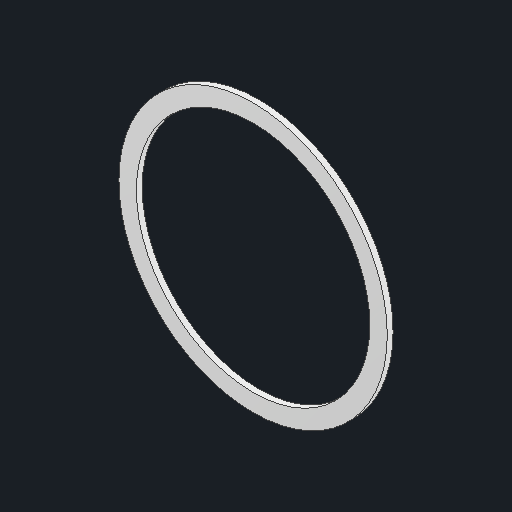
# Autodesk Inventor part: latitude_scale
Saved by Autodesk Inventor 2027.1 (Build 311270010, 270A)
## iProperties
Created: 2026-11-03
Part Number: latitude_scale
Material: Generic
Description: Latitude scale ring
Document SubType Name: Modeling
Designer: Claude (from photos)
Density: 1 g/cm^3
Appearance: Smooth - White
Author: alexg
Autodesk Inventor part; units mm, degrees
ref_plane "YZ Plane" through (0, 0, 0) normal (1, 0, 0) x (0, 1, 0)
ref_plane "XZ Plane" through (0, 0, 0) normal (0, 1, 0) x (-1, 0, 0)
ref_plane "Work Plane1" through (0, 0, -39) normal (0, 0, 1) x (1, 0, 0)
sketch "Latitude scale 0-90 sketch" plane through (0, 0, -39) normal (0, 0, 1) x (1, 0, 0)
  circle A0 centre (0, 64) radius 23
  circle A1 centre (0, 64) radius 20
  constraints: 2 centre point
extrude "Latitude scale 0-90" add sketch "Latitude scale 0-90 sketch" against normal blind 1
body "Solid1"
